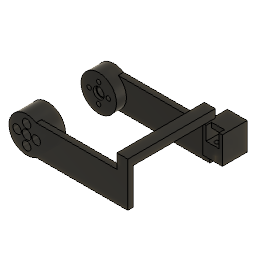
01_yoke_rotary_clearance_V5_editable (Autodesk Fusion 360 design; units mm, degrees)
part number: 2026-10-21-21-44-35-248
Autodesk Fusion 360 part; units mm, degrees
ref_plane "作業平面1" through (0, -32.5, 0) normal (0, 1, 0) x (0, 0, 1)
sketch "スケッチ1" plane through (0, -32.5, 0) normal (0, 1, 0) x (1, 0, 0)
  circle A0 centre (-2, -34) radius 13
  dimension "d1156" = 26
  measures "d1156" diameter of A0
extrude "V5_negative_horn_mount (1)" add sketch "スケッチ1" along normal blind 15.45
ref_plane "作業平面2" through (0, 0, 23) normal (0, 0, 1) x (1, 0, 0)
sketch "スケッチ2" plane through (0, 0, 23) normal (0, 0, 1) x (1, 0, 0)
  line L0 (-2, -32.5) -> (72, -32.5)
  line L1 (72, -32.5) -> (72, -28.5)
  line L2 (72, -28.5) -> (-2, -28.5)
  line L3 (-2, -28.5) -> (-2, -32.5)
extrude "V5_negative_outboard_rail (1)" add sketch "スケッチ2" along normal blind 22
ref_plane "作業平面3" through (0, 0, 23) normal (0, 0, 1) x (1, 0, 0)
sketch "スケッチ3" plane through (0, 0, 23) normal (0, 0, 1) x (1, 0, 0)
  line L0 (64, -32.5) -> (72, -32.5)
  line L1 (72, -32.5) -> (72, -28.5)
  line L2 (72, -28.5) -> (64, -28.5)
  line L3 (64, -28.5) -> (64, -32.5)
extrude "V5_negative_front_upright (1)" add sketch "スケッチ3" along normal blind 32.5
ref_plane "作業平面4" through (0, 0, 49.5) normal (0, 0, 1) x (1, 0, 0)
sketch "スケッチ4" plane through (0, 0, 49.5) normal (0, 0, 1) x (1, 0, 0)
  line L0 (64, -32.5) -> (72, -32.5)
  line L1 (72, -32.5) -> (72, 31.5)
  line L2 (72, 31.5) -> (64, 31.5)
  line L3 (64, 31.5) -> (64, -32.5)
extrude "V5_overhead_tie (1)" add sketch "スケッチ4" along normal blind 6
ref_plane "作業平面5" through (0, 0, 23) normal (0, 0, 1) x (1, 0, 0)
sketch "スケッチ5" plane through (0, 0, 23) normal (0, 0, 1) x (1, 0, 0)
  line L0 (64, 27.5) -> (72, 27.5)
  line L1 (72, 27.5) -> (72, 31.5)
  line L2 (72, 31.5) -> (64, 31.5)
  line L3 (64, 31.5) -> (64, 27.5)
extrude "V5_positive_front_upright (1)" add sketch "スケッチ5" along normal blind 32.5
ref_plane "作業平面6" through (0, 0, 23) normal (0, 0, 1) x (1, 0, 0)
sketch "スケッチ6" plane through (0, 0, 23) normal (0, 0, 1) x (1, 0, 0)
  line L0 (-2, 27.5) -> (72, 27.5)
  line L1 (72, 27.5) -> (72, 31.5)
  line L2 (72, 31.5) -> (-2, 31.5)
  line L3 (-2, 31.5) -> (-2, 27.5)
extrude "V5_positive_outboard_rail (1)" add sketch "スケッチ6" along normal blind 22
ref_plane "作業平面7" through (0, 20.2, 0) normal (0, 1, 0) x (0, 0, 1)
sketch "スケッチ7" plane through (0, 20.2, 0) normal (0, 1, 0) x (1, 0, 0)
  circle A0 centre (-2, -34) radius 13
  dimension "d1181" = 26
  measures "d1181" diameter of A0
extrude "V5_positive_horn_mount (1)" add sketch "スケッチ7" along normal blind 11.3
ref_plane "作業平面8" through (0, -32.6, 0) normal (0, 1, 0) x (0, 0, 1)
sketch "スケッチ8" plane through (0, -32.6, 0) normal (0, 1, 0) x (1, 0, 0)
  circle A0 centre (-2, -34) radius 3.25
  dimension "d1186" = 6.5
  measures "d1186" diameter of A0
extrude "V5_negative_center_key_access (1)" cut sketch "スケッチ8" along normal blind 15.65
ref_plane "作業平面9" through (0, -18.9, 0) normal (0, 1, 0) x (0, 0, 1)
sketch "スケッチ9" plane through (0, -18.9, 0) normal (0, 1, 0) x (1, 0, 0)
  circle A0 centre (-2, -34) radius 4
  dimension "d1191" = 8
  measures "d1191" diameter of A0
extrude "V5_negative_center_head_relief (1)" cut sketch "スケッチ9" along normal blind 1.9
ref_plane "作業平面10" through (0, -18.2, 0) normal (0, 1, 0) x (0, 0, 1)
sketch "スケッチ10" plane through (0, -18.2, 0) normal (0, 1, 0) x (1, 0, 0)
  circle A0 centre (-2, -34) radius 5.5
  dimension "d1196" = 11
  measures "d1196" diameter of A0
extrude "V5_fixed_motor_boss_clearance (1)" cut sketch "スケッチ10" along normal blind 1.2
ref_plane "作業平面11" through (0, -32.6, 0) normal (0, 1, 0) x (0, 0, 1)
sketch "スケッチ11" plane through (0, -32.6, 0) normal (0, 1, 0) x (1, 0, 0)
  circle A0 centre (5, -34) radius 1.6
  circle A1 centre (-2, -41) radius 1.6
  circle A2 centre (-9, -34) radius 1.6
  circle A3 centre (-2, -27) radius 1.6
  dimension "d1201" = 3.2
  dimension "d1202" = 3.2
  dimension "d1203" = 3.2
  dimension "d1204" = 3.2
  measures "d1201" diameter of A0
  measures "d1202" diameter of A1
  measures "d1203" diameter of A2
  measures "d1204" diameter of A3
extrude "V5_negative_radial_pitch14_M3" cut sketch "スケッチ11" along normal blind 15.65
ref_plane "作業平面12" through (0, -32.6, 0) normal (0, 1, 0) x (0, 0, 1)
sketch "スケッチ12" plane through (0, -32.6, 0) normal (0, 1, 0) x (1, 0, 0)
  circle A0 centre (5, -34) radius 3.1
  circle A1 centre (-2, -41) radius 3.1
  circle A2 centre (-9, -34) radius 3.1
  circle A3 centre (-2, -27) radius 3.1
  dimension "d1209" = 6.2
  dimension "d1210" = 6.2
  dimension "d1211" = 6.2
  dimension "d1212" = 6.2
  measures "d1209" diameter of A0
  measures "d1210" diameter of A1
  measures "d1211" diameter of A2
  measures "d1212" diameter of A3
extrude "V5_negative_M3_head_counterbores" cut sketch "スケッチ12" along normal blind 5.6
ref_plane "作業平面13" through (0, 20.1, 0) normal (0, 1, 0) x (0, 0, 1)
sketch "スケッチ13" plane through (0, 20.1, 0) normal (0, 1, 0) x (1, 0, 0)
  circle A0 centre (-2, -34) radius 3.25
  dimension "d1217" = 6.5
  measures "d1217" diameter of A0
extrude "V5_positive_center_key_access (1)" cut sketch "スケッチ13" along normal blind 11.5
ref_plane "作業平面14" through (0, 20.1, 0) normal (0, 1, 0) x (0, 0, 1)
sketch "スケッチ14" plane through (0, 20.1, 0) normal (0, 1, 0) x (1, 0, 0)
  circle A0 centre (-2, -34) radius 4
  dimension "d1222" = 8
  measures "d1222" diameter of A0
extrude "V5_positive_center_head_relief (1)" cut sketch "スケッチ14" along normal blind 2.1
ref_plane "作業平面15" through (0, 20.1, 0) normal (0, 1, 0) x (0, 0, 1)
sketch "スケッチ15" plane through (0, 20.1, 0) normal (0, 1, 0) x (1, 0, 0)
  circle A0 centre (5, -34) radius 1.6
  circle A1 centre (-2, -41) radius 1.6
  circle A2 centre (-9, -34) radius 1.6
  circle A3 centre (-2, -27) radius 1.6
  dimension "d1227" = 3.2
  dimension "d1228" = 3.2
  dimension "d1229" = 3.2
  dimension "d1230" = 3.2
  measures "d1227" diameter of A0
  measures "d1228" diameter of A1
  measures "d1229" diameter of A2
  measures "d1230" diameter of A3
extrude "V5_positive_radial_pitch14_M3" cut sketch "スケッチ15" along normal blind 11.5
ref_plane "作業平面16" through (0, 28, 0) normal (0, 1, 0) x (0, 0, 1)
sketch "スケッチ16" plane through (0, 28, 0) normal (0, 1, 0) x (1, 0, 0)
  circle A0 centre (5, -34) radius 3.1
  circle A1 centre (-2, -41) radius 3.1
  circle A2 centre (-9, -34) radius 3.1
  circle A3 centre (-2, -27) radius 3.1
  dimension "d1235" = 6.2
  dimension "d1236" = 6.2
  dimension "d1237" = 6.2
  dimension "d1238" = 6.2
  measures "d1235" diameter of A0
  measures "d1236" diameter of A1
  measures "d1237" diameter of A2
  measures "d1238" diameter of A3
extrude "V5_positive_M3_head_counterbores" cut sketch "スケッチ16" along normal blind 3.6
ref_plane "作業平面17" through (0, 0, 29.5) normal (0, 0, 1) x (1, 0, 0)
sketch "スケッチ17" plane through (0, 0, 29.5) normal (0, 0, 1) x (1, 0, 0)
  line L0 (70.8, 23.4629) -> (85.2, 23.4629)
  line L1 (85.2, 23.4629) -> (85.2, 41.5629)
  line L2 (85.2, 41.5629) -> (70.8, 41.5629)
  line L3 (70.8, 41.5629) -> (70.8, 23.4629)
extrude "V5_fixed_cell_platform (1)" add sketch "スケッチ17" along normal blind 10
ref_plane "作業平面18" through (0, 0, 39.5) normal (0, 0, 1) x (1, 0, 0)
sketch "スケッチ18" plane through (0, 0, 39.5) normal (0, 0, 1) x (1, 0, 0)
  line L0 (70.8, 23.4629) -> (73.3, 23.4629)
  line L1 (73.3, 23.4629) -> (73.3, 41.5629)
  line L2 (73.3, 41.5629) -> (70.8, 41.5629)
  line L3 (70.8, 41.5629) -> (70.8, 23.4629)
extrude "V5_fixed_socket_wall_70.8 (1)" add sketch "スケッチ18" along normal blind 10
ref_plane "作業平面19" through (0, 0, 39.5) normal (0, 0, 1) x (1, 0, 0)
sketch "スケッチ19" plane through (0, 0, 39.5) normal (0, 0, 1) x (1, 0, 0)
  line L0 (82.7, 23.4629) -> (85.2, 23.4629)
  line L1 (85.2, 23.4629) -> (85.2, 41.5629)
  line L2 (85.2, 41.5629) -> (82.7, 41.5629)
  line L3 (82.7, 41.5629) -> (82.7, 23.4629)
extrude "V5_fixed_socket_wall_82.7 (1)" add sketch "スケッチ19" along normal blind 10
ref_plane "作業平面20" through (0, 0, 45.9) normal (0, 0, 1) x (1, 0, 0)
sketch "スケッチ20" plane through (0, 0, 45.9) normal (0, 0, 1) x (1, 0, 0)
  line L0 (70.8, 27.4629) -> (85.2, 27.4629)
  line L1 (85.2, 27.4629) -> (85.2, 41.5629)
  line L2 (85.2, 41.5629) -> (70.8, 41.5629)
  line L3 (70.8, 41.5629) -> (70.8, 27.4629)
extrude "V5_fixed_socket_roof (1)" add sketch "スケッチ20" along normal blind 3.6
ref_plane "作業平面21" through (0, 0, 39.5) normal (0, 0, 1) x (1, 0, 0)
sketch "スケッチ21" plane through (0, 0, 39.5) normal (0, 0, 1) x (1, 0, 0)
  line L0 (73.3, 38.8629) -> (82.7, 38.8629)
  line L1 (82.7, 38.8629) -> (82.7, 41.5629)
  line L2 (82.7, 41.5629) -> (73.3, 41.5629)
  line L3 (73.3, 41.5629) -> (73.3, 38.8629)
extrude "V5_fixed_socket_end_stop (1)" add sketch "スケッチ21" along normal blind 6.4
ref_plane "作業平面22" through (0, 0, 29.5) normal (0, 0, 1) x (1, 0, 0)
sketch "スケッチ22" plane through (0, 0, 29.5) normal (0, 0, 1) x (1, 0, 0)
  circle A0 centre (78, 26.9629) radius 1.7
  circle A1 centre (78, 34.3629) radius 1.7
  dimension "d1263" = 3.4
  dimension "d1264" = 3.4
  measures "d1263" diameter of A0
  measures "d1264" diameter of A1
extrude "V5_fixed_M3_clearance (1)" cut sketch "スケッチ22" along normal blind 10
ref_plane "作業平面23" through (0, 0, 29.5) normal (0, 0, 1) x (1, 0, 0)
sketch "スケッチ23" plane through (0, 0, 29.5) normal (0, 0, 1) x (1, 0, 0)
  circle A0 centre (78, 26.9629) radius 3.1
  circle A1 centre (78, 34.3629) radius 3.1
  dimension "d1269" = 6.2
  dimension "d1270" = 6.2
  measures "d1269" diameter of A0
  measures "d1270" diameter of A1
extrude "V5_fixed_M3_heads (1)" cut sketch "スケッチ23" along normal blind 3.2
equation "d1263 = sc_screw_clearance"
equation "d1264 = sc_screw_clearance"
equation "d1269 = sc_head_dia"
equation "d1270 = sc_head_dia"
equation "d1271 = sc_head_depth"
equation "sc_screw_clearance = 3.4 mm" comment "Printed base M3 clearance; sensor itself has M3 threaded holes"
equation "sc_head_dia = 6.2 mm" comment "Underside socket-head recess diameter"
equation "sc_head_depth = 3.2 mm" comment "Underside socket-head recess depth; M3x8 gives 5.2 mm engagement"
named bodies: "V5_one_piece_yoke_M3_clearance_slide_socket"
